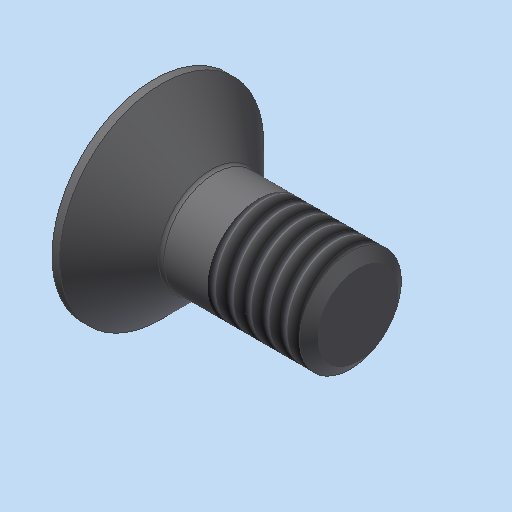
# Autodesk Inventor part: Senkschraube_DIN_7991___M4x8
Saved by Autodesk Inventor 2023.3 (Build 273359000, 359)
## iProperties
Shininess: 64.0
Length Units: 11269
Angle Units: 11279
Time Units: 11290
Mass Units: 11283
Length Display Precision: 3
Angle Display Precision: 2
Compacted: True
Part Number: Senkschraube_DIN_7991___M4x8
Document SubType Name: Modeling
Created: 2004-03-28
Material: xStahl_AnP_Dummymaterial
Description: =<RBPARTNOTITLE2>
Vendor: NORM8
Designer: S.Riedelsheimer
Manufacturer: Standard
Standards Organization: Custom
Density: 7.85 g/cm^3
Mass: 1.04813 g
Surface Area: 2.07831 cm^2
Volume: 0.13352 cm^3
Appearance: Stahl - normal AnP
DOC_ID: 5 F45 Senkschraube_DIN_7991___M4x8
GAIN_REFID: 20__Senkschraube_DIN_7991___M4x8:81C07
Control State: 0
Master: False
Checked Out: False
CNS_NB: Senkschraube DIN 7991 - M4x8
CNS_NN: DIN 7991
CNS_NT: Senkschraube mit Innensechskant
CNS_NBSYN: Senkschraube DIN 7991 - $NENN.
CNS_LINA: Senkschraube DIN 7991 - M4x8
CNS_NENN: M4x8
CNS_D: 4.000
CNS_D3: 3.141
CNS_P: 0.700
CNS_L: 8.000
CNS_S: 2.500
CNS_DK: 8.000
CNS_AL: 90.000
CNS_DS: 4.000
CNS_K: 2.300
CNS_R: 0.200
CNS_T: 1.800
CNS_LS: 2.500
CNS_LG: 4.400
CNS_YW: 1.571
CNS_YC: 0.300
CNS_KT: L
PSOL_IDENT_0: {C:\partsolutions8\data\23d-libs\bosch_bamberg\schrauben\senkschrauben\din_7991.prj},164 {M=Nenngewi
PSOL_IDENT_1: nde},{VTYP=3D},{NB=Senkschraube DIN 7991 - M4x8},{NN=DIN 7991},{DATE=26.11.2003},{GEOMDATE=26.11.200
PSOL_IDENT_2: 3},{VERSION=v1},{LINEID=80},{LINESUBID=-1},{WBVAR=}  {NB=Senkschraube DIN 7991 - M4x8},{LINA=Senksch
PSOL_IDENT_3: raube DIN 7991 - M4x8},{KT=L},{IDNR=},{NENN=M4x8},{D=4.000},{D3=3.141},{P=0.700},{L=8.000},{S=2.500}
PSOL_IDENT_4: ,{DK=8.000},{AL=90.000},{DS=4.000},{K=2.300},{R=0.200},{T=1.800},{LS=2.500},{LG=4.400},{YW=1.57079},
PSOL_IDENT_5: {YC=0.299988}
DEF_STKID: T21278
Bezeichnung1: Senkschraube DIN 7991 - M4x8
Bezeichnung2: Senkschraube mit Innensechskant
RBDRAWINGMISSINGSPEC: --
RBPARTNOTITLE1: Hexagon socket countersunk head screws
RBPARTNOTITLE2: Senkschraube mit Innensechskant
AnP_Kategorie: 4
RBPARTMADEOF: DIN 7991 - M4x8 - 8.8 - verzinkt
Density: 0.0
Volumn: 0.0
Area: 0.0
PropertySet Name: Model Information
Title: Senkschraube DIN 7991 - M4x8
Author: S.Riedelsheimer
Keywords: =<RBPARTMADEOF>
Comments: =<RBSURFACE2>
Revision Number: 01
Autodesk Inventor part; units mm, degrees
sketch "Schraube" plane through (0, 0, 0) normal (0, 1, 0) x (-1, 0, 0)
  line L0 (-8, 0) -> (-3.45, 0)
  line L1 (-2.5145, 0) -> (-1.8, -1.2375)
  line L2 (-1.8, -1.2375) -> (-0.278, -1.2375)
  line L3 (-0.278, -1.2375) -> (0, -1.5155)
  line L4 (0, -1.5155) -> (0, -4)
  line L5 (0, -4) -> (-0.3, -4)
  line L6 (-0.3, -4) -> (-2.2414, -2.0586)
  arc A0 (-2.2414, -2.0586) -> (-2.3828, -2) centre (-2.3828, -2.2) ccw
  line L7 (-2.3828, -2) -> (-7.6963, -2)
  line L8 (-7.6963, -2) -> (-8, -1.5705)
  line L9 (-8, -1.5705) -> (-8, 0)
  line L10 (-8, 0) -> (-2.5145, 0)
  constraints: 22 end point, 2 point on circle, 1 centre point
revolve "Drehung1" add sketch "Schraube" angle 360 about axis through (8, 0, 0) along (1, 0, 0)
thread "Gewinde1" size "M4x0.7" class "6g" standard "ANSI Metric M Profile" length 3.6
sketch "Sketch_1" plane through (0, 0, 0) normal (1, 0, 0) x (0, 1, 0)
  line L0 (0.7195, 1.2513) -> (-0.7239, 1.2487)
  line L1 (-0.7239, 1.2487) -> (-1.4434, -0.0025)
  line L2 (-1.4434, -0.0025) -> (-0.7195, -1.2513)
  line L3 (-0.7195, -1.2513) -> (0.7239, -1.2487)
  line L4 (0.7239, -1.2487) -> (1.4434, 0.0025)
  line L5 (1.4434, 0.0025) -> (0.7195, 1.2513)
  constraints: 12 end point
extrude "Extrusion1" cut sketch "Sketch_1" along normal blind 1.8
ref_plane "IP2_XY" through (0, 0, 0) normal (1, 0, 0) x (0, 0, -1)
ref_plane "IP2_YZ" through (0, 0, 0) normal (0, 0, -1) x (0, 1, 0)
ref_plane "IP3_XY" through (8, 0, 0) normal (1, 0, 0) x (0, 0, -1)
ref_plane "IP3_YZ" through (8, 0, 0) normal (0, 0, -1) x (0, 1, 0)
